Autodesk Inventor part; units mm, degrees
(part 2 of 2)
sketch "Sketch6" plane through (5.0265, 0, 24.4895) normal (0.2010598, 0, 0.979579) x (0, 1, 0)
  line L0 (8.6989, -14.3968) -> (1.8014, -14.3968)
  line L1 (1.8014, -14.3968) -> (1.8014, 11.6142)
  line L2 (1.8014, 11.6142) -> (8.6989, 11.6142)
  line L3 (8.6989, 11.6142) -> (8.6989, -14.3968)
  line L4 (3.1013, 7.5895) -> (3.1013, 8.5295)
  line L5 (3.1013, 8.5295) -> (6.1192, 8.5295)
  line L6 (6.1192, 8.5295) -> (6.1192, 7.5895)
  line L7 (6.1192, 7.5895) -> (3.1013, 7.5895)
  line L8 (6.5503, 7.5603) -> (6.5503, 8.5555)
  line L9 (6.5503, 8.5555) -> (7.2829, 8.5555)
  line L10 (7.2829, 8.5555) -> (7.2829, 7.5603)
  line L11 (7.2829, 7.5603) -> (6.5503, 7.5603)
  spline S0 degree 2 poles (5.8404, 3.7386) (5.5616, 3.7386) (5.056, 3.9169) (4.8874, 4.0822) knots 0 0 0 1 2 2 2
  spline S1 degree 2 poles (4.8874, 4.0822) (4.7804, 4.1827) (4.6054, 4.429) (4.5438, 4.5749) knots 0 0 0 1 2 2 2
  spline S2 degree 2 poles (4.5438, 4.5749) (4.4822, 4.724) (4.4109, 5.0709) (4.4109, 5.2848) knots 0 0 0 1 2 2 2
  line L12 (4.4109, 5.2848) -> (4.4109, 5.8099)
  line L13 (4.4109, 5.8099) -> (3.1013, 5.8099)
  line L14 (3.1013, 5.8099) -> (3.1013, 6.8148)
  line L15 (3.1013, 6.8148) -> (7.1013, 6.8148)
  line L16 (7.1013, 6.8148) -> (7.1013, 5.2621)
  spline S3 degree 2 poles (7.1013, 5.2621) (7.1013, 4.9185) (6.9749, 4.4161) (6.8388, 4.2119) knots 0 0 0 1 2 2 2
  spline S4 degree 2 poles (6.8388, 4.2119) (6.6864, 3.985) (6.1872, 3.7386) (5.8404, 3.7386) knots 0 0 0 1 2 2 2
  spline S5 degree 2 poles (5.8145, 4.7694) (5.9863, 4.7694) (6.2294, 4.9315) (6.2748, 5.0417) knots 0 0 0 1 2 2 2
  spline S6 degree 2 poles (6.2748, 5.0417) (6.3363, 5.1843) (6.3558, 5.4436) (6.3558, 5.6673) knots 0 0 0 1 2 2 2
  line L17 (6.3558, 5.6673) -> (6.3558, 5.8099)
  line L18 (6.3558, 5.8099) -> (5.1564, 5.8099)
  line L19 (5.1564, 5.8099) -> (5.1564, 5.7386)
  spline S7 degree 2 poles (5.1564, 5.7386) (5.1564, 5.5992) (5.1629, 5.3464) (5.1791, 5.2524) knots 0 0 0 1 2 2 2
  spline S8 degree 2 poles (5.1791, 5.2524) (5.1921, 5.1713) (5.2699, 4.9931) (5.3185, 4.9444) knots 0 0 0 1 2 2 2
  spline S9 degree 2 poles (5.3185, 4.9444) (5.4158, 4.8407) (5.6329, 4.7694) (5.8145, 4.7694) knots 0 0 0 1 2 2 2
  spline S10 degree 2 poles (5.1013, -0.4397) (4.1289, -0.4397) (3.0171, 0.5976) (3.0171, 1.4987) knots 0 0 0 1 2 2 2
  spline S11 degree 2 poles (3.0171, 1.4987) (3.0171, 2.4031) (4.1419, 3.4339) (5.1013, 3.4339) knots 0 0 0 1 2 2 2
  spline S12 degree 2 poles (5.1013, 3.4339) (6.0641, 3.4339) (7.1856, 2.4031) (7.1856, 1.4987) knots 0 0 0 1 2 2 2
  spline S13 degree 2 poles (7.1856, 1.4987) (7.1856, 0.5976) (6.0705, -0.4397) (5.1013, -0.4397) knots 0 0 0 1 2 2 2
  spline S14 degree 2 poles (5.1013, 0.5976) (5.4611, 0.5976) (5.9636, 0.7435) (6.1224, 0.8699) knots 0 0 0 1 2 2 2
  spline S15 degree 2 poles (6.1224, 0.8699) (6.2877, 0.9963) (6.4303, 1.3205) (6.4303, 1.4955) knots 0 0 0 1 2 2 2
  spline S16 degree 2 poles (6.4303, 1.4955) (6.4303, 1.6803) (6.2974, 1.9817) (6.1289, 2.1211) knots 0 0 0 1 2 2 2
  spline S17 degree 2 poles (6.1289, 2.1211) (5.9733, 2.2443) (5.4579, 2.3966) (5.1013, 2.3966) knots 0 0 0 1 2 2 2
  spline S18 degree 2 poles (5.1013, 2.3966) (4.7318, 2.3966) (4.2456, 2.2508) (4.0803, 2.1243) knots 0 0 0 1 2 2 2
  spline S19 degree 2 poles (4.0803, 2.1243) (3.9149, 1.9979) (3.7723, 1.6705) (3.7723, 1.4955) knots 0 0 0 1 2 2 2
  spline S20 degree 2 poles (3.7723, 1.4955) (3.7723, 1.3172) (3.9247, 0.9866) (4.0867, 0.8666) knots 0 0 0 1 2 2 2
  spline S21 degree 2 poles (4.0867, 0.8666) (4.2618, 0.737) (4.7253, 0.5976) (5.1013, 0.5976) knots 0 0 0 1 2 2 2
  line L20 (7.1013, -6.1933) -> (3.1013, -5.182)
  line L21 (3.1013, -5.182) -> (3.1013, -4.0799)
  line L22 (3.1013, -4.0799) -> (5.5746, -3.4381)
  line L23 (5.5746, -3.4381) -> (3.1013, -2.8189)
  line L24 (3.1013, -2.8189) -> (3.1013, -1.7136)
  line L25 (3.1013, -1.7136) -> (7.1013, -0.7022)
  line L26 (7.1013, -0.7022) -> (7.1013, -1.746)
  line L27 (7.1013, -1.746) -> (4.4239, -2.2971)
  line L28 (4.4239, -2.2971) -> (7.1013, -2.9648)
  line L29 (7.1013, -2.9648) -> (7.1013, -3.9632)
  line L30 (7.1013, -3.9632) -> (4.4206, -4.5985)
  line L31 (4.4206, -4.5985) -> (7.1013, -5.1755)
  line L32 (7.1013, -5.1755) -> (7.1013, -6.1933)
  line L33 (3.1013, -6.6893) -> (7.1013, -6.6893)
  line L34 (7.1013, -6.6893) -> (7.1013, -9.3927)
  line L35 (7.1013, -9.3927) -> (6.3396, -9.3927)
  line L36 (6.3396, -9.3927) -> (6.3396, -7.6877)
  line L37 (6.3396, -7.6877) -> (5.6362, -7.6877)
  line L38 (5.6362, -7.6877) -> (5.6362, -9.2598)
  line L39 (5.6362, -9.2598) -> (4.8744, -9.2598)
  line L40 (4.8744, -9.2598) -> (4.8744, -7.6877)
  line L41 (4.8744, -7.6877) -> (3.8631, -7.6877)
  line L42 (3.8631, -7.6877) -> (3.8631, -9.3927)
  line L43 (3.8631, -9.3927) -> (3.1013, -9.3927)
  line L44 (3.1013, -9.3927) -> (3.1013, -6.6893)
  line L45 (3.1013, -13.7687) -> (3.1013, -12.5466)
  line L46 (3.1013, -12.5466) -> (4.5697, -11.4348)
  line L47 (4.5697, -11.4348) -> (4.5697, -11.0718)
  line L48 (4.5697, -11.0718) -> (3.1013, -11.0718)
  line L49 (3.1013, -11.0718) -> (3.1013, -10.0734)
  line L50 (3.1013, -10.0734) -> (7.1013, -10.0734)
  line L51 (7.1013, -10.0734) -> (7.1013, -11.6812)
  spline S22 degree 2 poles (7.1013, -11.6812) (7.1013, -12.015) (7.0171, -12.5077) (6.8874, -12.7184) knots 0 0 0 1 2 2 2
  spline S23 degree 2 poles (6.8874, -12.7184) (6.7513, -12.9324) (6.3266, -13.1852) (6.0025, -13.1852) knots 0 0 0 1 2 2 2
  spline S24 degree 2 poles (6.0025, -13.1852) (5.5454, -13.1852) (4.9717, -12.7703) (4.8031, -12.4235) knots 0 0 0 1 2 2 2
  line L52 (4.8031, -12.4235) -> (3.1013, -13.7687)
  spline S25 degree 2 poles (5.876, -12.1544) (6.0284, -12.1544) (6.2456, -12.0377) (6.3039, -11.9048) knots 0 0 0 1 2 2 2
  spline S26 degree 2 poles (6.3039, -11.9048) (6.3428, -11.8108) (6.3655, -11.5807) (6.3655, -11.4089) knots 0 0 0 1 2 2 2
  line L53 (6.3655, -11.4089) -> (6.3655, -11.0718)
  line L54 (6.3655, -11.0718) -> (5.2893, -11.0718)
  line L55 (5.2893, -11.0718) -> (5.2893, -11.3603)
  spline S27 degree 2 poles (5.2893, -11.3603) (5.2893, -11.5677) (5.3412, -11.8627) (5.4222, -11.9632) knots 0 0 0 1 2 2 2
  spline S28 degree 2 poles (5.4222, -11.9632) (5.5, -12.0604) (5.7075, -12.1544) (5.876, -12.1544) knots 0 0 0 1 2 2 2
  point P0 (0, 0)
  point P1 (7.2829, 8.8893)
  dimension "d0" = 50
  dimension "d1" = 3.17
  dimension "d2" = 8
  dimension "d3" = 16
  dimension "d6" = 360
  dimension "d10" = 2
  dimension "d11" = 2
  dimension "d12" = 2
  dimension "d13" = 2
  dimension "d86" = 12
  constraints: 8 end point, 2 parallel, 1 horizontal, 1 perpendicular, 1 other
emboss "Emboss2" sketch "Sketch6" operation add depth 0.01 direction (-0.2010598, 0, -0.979579) wrap yes faces at (15.8314, 4.8266, 19.3486) contours L4 L5 L6 L7 | L8 L9 L10 L11 | S0 S1 S2 L12 L13 L14 L15 L16 S3 S4 | S10 S11 S12 S13 | L20 L21 L22 L23 L24 L25 L26 L27 L28 L29 L30 L31 L32 | L33 L34 L35 L36 L37 L38 L39 L40 L41 L42 L43 L44 | L45 L46 L47 L48 L49 L50 L51 S22 S23 S24 L52
equation "\"d11\" = d10"
equation "\"d12\" = d10"
equation "\"d13\" = d10"
body "Solid2"
body "Solid3"
